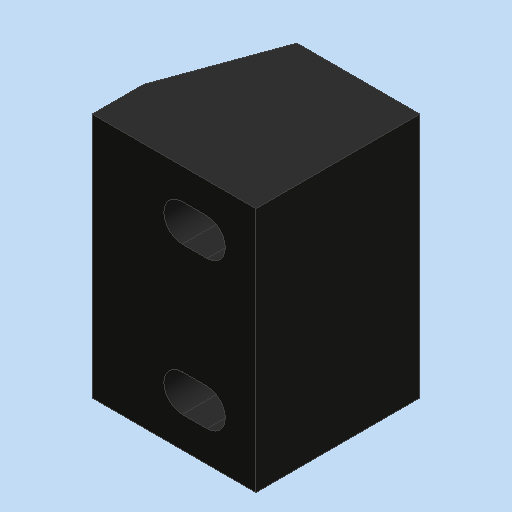
# Autodesk Inventor part: MM0948AN160_G01_115
Saved by Autodesk Inventor 2023.3 (Build 273359000, 359)
## iProperties
RuleStatus: InUse
Created: 2023-03-23
Part Number: MM0948AN160_G01_115
Material: Kst - Murtfeldt S schwarz
Description: =<RBPARTNOTITLE2>
Document SubType Name: Modeling
Designer: ric7an
Mass: 8.37202 g
Surface Area: 38.6842 cm^2
Volume: 9.00217 cm^3
Density: 0.93 g/cm^3
Appearance: schwarz AnP
AnP_Kategorie: 1
AnP_Material: =<Material>
MaxAbmaße: 30 x 20 x 20 (FM)
AnP_TemplVers: 20200821
RBDOCUMENTTYPE: DRF
RBDOCUMENTVERSION: 00
RBDRAWINGMAINSCALE: 1:1
RBDRAWINGMISSINGSPEC: --
RBDRAWINGVOLUME: --
RBDSV1: 0850
RBGBEDGESIN1: +0,5
RBGBEDGESIN2: +0,2
RBGBEDGESOUT1: -0,3
RBGBEDGESOUT2: -0,1
RBMATERIAL: =<Material>
RBMATMEETS: --
RBMATNO: =<Part Number>
RBPARTMADEOF: 30 x 20 x 20 (FM)
RBPARTNO: SIEHE MNR
RBPARTNOTITLE1: manufactured part
RBPARTNOTITLE2: Anfertigungsteil
RBPARTSAFETYINDICATOR: --
RBSURFACE: --
RBSURFACE2: --
RBZEDGESNORM: ISO13715:2002-06
RBZGENDIMCLASS: m
RBZGENDIMNORM: ISO 2768-1:1989-11
RBZGENGEOCLASS: H
RBZGENGEONORM: ISO 2768-2:1989-11
RBZSURFACENORM: ISO13D2:2002-02
RBZTOLERANCENORM: ISO 14405-1:2010-12
AnP_Kommentar_aktuell: =<Comments>
AnP_Material_aktuell: =<Material>
Author: FH/Wi
Keywords: =<RBPARTMADEOF>
Comments: =<RBSURFACE2>
Revision Number: 01
Autodesk Inventor part; units mm, degrees
ref_plane "YZ Plane" through (0, 0, 0) normal (1, 0, 0) x (0, 1, 0)
ref_plane "XZ Plane" through (0, 0, 0) normal (0, 1, 0) x (-1, 0, 0)
ref_plane "XY Plane" through (0, 0, 0) normal (0, 0, 1) x (1, 0, 0)
sketch "Skizze1" plane through (0, 0, 0) normal (0, 0, 1) x (1, 0, 0)
  line L0 (0, 0) -> (20, 0)
  line L1 (20, 0) -> (20, 20)
  line L2 (20, 20) -> (0, 20)
  line L3 (0, 20) -> (0, 0)
  line L4 (5, 20) -> (0, 6.2626)
  dimension "d0" = 20
  dimension "d1" = 5
  dimension "d2" = 20
  dimension "d3" = 20
  constraints: 10 end point, 2 parallel, 2 point on line, 1 horizontal, 1 perpendicular
  measures "d0" angle of L3 L4
  measures "d1" distance from line of L3 L4.start
  measures "d2" distance of L1.end L2.end
  measures "d3" distance of L0.end L1.end
extrude "Extrusion1" add sketch "Skizze1" along normal mid plane 30 contours L3 L4 L2 L1 L0
sketch "Skizze2" plane through (5, 20, 15) normal (0, 1, 0) x (1, 0, 0)
  line L0 (6, 24) -> (9, 24) construction
  line L1 (6, 26.25) -> (9, 26.25)
  line L2 (9, 21.75) -> (6, 21.75)
  arc A0 (6, 26.25) -> (6, 21.75) centre (6, 24) ccw
  arc A1 (9, 21.75) -> (9, 26.25) centre (9, 24) ccw
  line L3 (6, 6) -> (9, 6) construction
  line L4 (6, 8.25) -> (9, 8.25)
  line L5 (9, 3.75) -> (6, 3.75)
  arc A2 (6, 8.25) -> (6, 3.75) centre (6, 6) ccw
  arc A3 (9, 3.75) -> (9, 8.25) centre (9, 6) ccw
  line L6 (-5, 36) -> (-5, -6) projected
  line L7 (19.2, 15) -> (-10.2, 15) projected
  line L8 (15, 0) -> (15, 30) projected
  point P0 (-5, 15)
  point P1 (7.5, 24)
  point P2 (7.5, 6)
  dimension "d6" = 3
  dimension "d7" = 4.5
  dimension "d8" = 4.5
  dimension "d9" = 18
  dimension "d10" = 7.5
  constraints: 16 end point, 8 point on circle, 8 tangent, 4 centre point, 3 parallel, 2 midpoint, 2 vertical alignment, 1 horizontal, 1 other
  measures "d6" distance of L0.start L0.end
  measures "d7" distance between parallel lines of L2 L1
  measures "d8" distance between parallel lines of L5 L4
  measures "d9" distance between parallel lines of L3 L0
  measures "d10" distance from line of L8 point (7.5, 6)
extrude "Extrusion2" cut sketch "Skizze2" against normal through all
sketch "Skizze3" plane through (5, 20, 15) normal (0, 1, 0) x (1, 0, 0)
  arc A0 (6, 26.25) -> (6, 21.75) centre (6, 24) ccw projected
  line L0 (6, 26.25) -> (9, 26.25) projected
  arc A1 (9, 21.75) -> (9, 26.25) centre (9, 24) ccw projected
  line L1 (9, 21.75) -> (6, 21.75) projected
  arc A2 (6, 8.25) -> (6, 3.75) centre (6, 6) ccw projected
  line L2 (6, 8.25) -> (9, 8.25) projected
  arc A3 (9, 3.75) -> (9, 8.25) centre (9, 6) ccw projected
  line L3 (9, 3.75) -> (6, 3.75) projected
  line L4 (0, 30) -> (0, 0) projected
  line L5 (15, 0) -> (0, 0) projected
  line L6 (15, 0) -> (15, 30) projected
  line L7 (0, 30) -> (15, 30) projected
  line L8 (6, 24) -> (9, 24) construction
  line L9 (6, 19) -> (9, 19)
  line L10 (9, 29) -> (6, 29)
  arc A4 (6, 29) -> (6, 19) centre (6, 24) ccw
  arc A5 (9, 19) -> (9, 29) centre (9, 24) ccw
  line L11 (6, 6) -> (9, 6) construction
  line L12 (6, 1) -> (9, 1)
  line L13 (9, 11) -> (6, 11)
  arc A6 (6, 11) -> (6, 1) centre (6, 6) ccw
  arc A7 (9, 1) -> (9, 11) centre (9, 6) ccw
  point P0 (-5, 15)
  point P1 (7.5, 24)
  point P2 (7.5, 6)
  dimension "d13" = 10
  dimension "d14" = 10
  constraints: 16 end point, 8 point on circle, 8 tangent, 4 centre point, 4 parallel, 2 midpoint, 1 coincident
  measures "d13" diameter of A5
  measures "d14" diameter of A7
extrude "Extrusion3" cut sketch "Skizze3" against normal blind 5 contours A4 L10 A5 L9 | A6 L13 A7 L12
equation "\"d8\" = d7"
equation "\"d13\" = d14"
